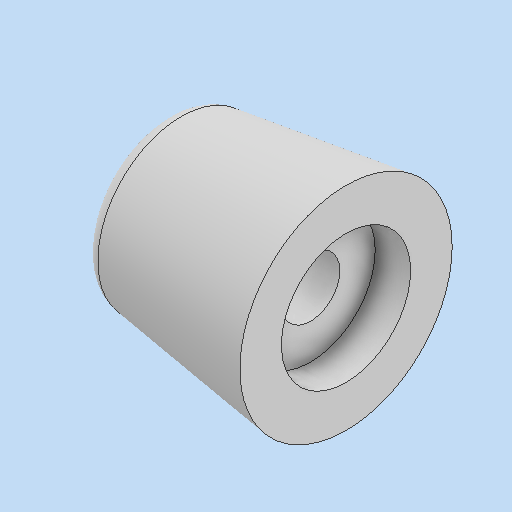
# Autodesk Inventor part: Pieza1
Saved by Autodesk Inventor 2026.3 (Build 303398000, 398)
## iProperties
Created: 2026-11-02
Part Number: Pieza1
Material: Genérico
Document SubType Name: Modeling
Designer: Hp
Density: 1 g/cm^3
Appearance: Valor por defecto
Author: Hp
Autodesk Inventor part; units mm, degrees
ref_plane "YZ Plane" through (0, 0, 0) normal (1, 0, 0) x (0, 1, 0)
ref_plane "XZ Plane" through (0, 0, 0) normal (0, 1, 0) x (-1, 0, 0)
ref_plane "XY Plane" through (0, 0, 0) normal (0, 0, 1) x (1, 0, 0)
sketch "Boceto1" plane through (0, 0, 0) normal (0, 1, 0) x (-1, 0, 0)
  line L0 (0, 0) -> (19.5, 0)
  line L1 (0, 0) -> (0, -12)
  line L2 (0, -12) -> (18.6258, -9.4331)
  arc A0 (18.6258, -9.4331) -> (20.301, -7) centre (18.3527, -7.4518) ccw
  line L3 (0, -7.3) -> (4, -7.3)
  line L4 (4, -7.3) -> (4, -3.3)
  line L5 (4, -3.3) -> (16, -3.3)
  line L6 (16, -3.3) -> (16, 0)
  line L7 (19.5, 0) -> (19.5, -3.6239) construction
  line L8 (16, 0) -> (19.5, 0)
  arc A1 (20.301, 7) -> (20.301, -7) centre (50.4869, 0) ccw
  point P0 (20, -8.586)
  point P1 (19.5, 0)
  dimension "d2" = 12
  dimension "d3" = 2
  dimension "d4" = 4
  dimension "d6" = 12
  dimension "d7" = 4
  dimension "d8" = 3.3
  dimension "d14" = 20
  dimension "d15" = 7
  dimension "d16" = 3.5
  constraints: 18 end point, 7 point on circle, 4 horizontal, 3 perpendicular, 2 centre point, 2 point on line, 2 tangent, 1 horizontal alignment, 1 vertical, 1 vertical alignment
  measures "d2" distance of L0.start L1.end
  measures "d3" radius of A0
  measures "d4" distance of L3.start L3.end
  measures "d6" distance of L4.end L5.end
  measures "d7" distance of L3.end L4.end
  measures "d8" distance of L5.end L6.end
  measures "d14" horizontal distance of L1.end point (20, -8.586)
  measures "d15" distance from line of L8 A0.end
  measures "d16" distance from line of point (19.5, 0) L6
revolve "Revolución1" add sketch "Boceto1" angle 360 about axis through (0, 0, 0) along (-1, 0, 0) contours L0 A1 A0 L2 L1 L3 L4 L5 L6
sketch "Boceto2" plane through (-16, 0, 0) normal (1, 0, 0) x (0, 0, -1)
  circle A0 centre (0, 0) radius 3.3 projected
  line L0 (-2.8284, 1.7) -> (2.8284, 1.7)
  line L1 (0, 1.7) -> (0, -3.3) construction
  point P0 (0, 0)
  dimension "d17" = 5
  constraints: 4 end point, 3 point on circle, 1 horizontal, 1 midpoint, 1 point on line, 1 vertical
  measures "d17" distance of L1.start L1.end
extrude "Extrusión1" add sketch "Boceto2" along normal blind 10.5 contours L0 A0 picked at (-0.1256, 2.2261)
